Untitled (Autodesk Fusion 360 design; units mm, degrees)
Autodesk Fusion 360 part; units mm, degrees
sketch "Sketch1" plane through (0, 0, 0) normal (0, 1, 0) x (1, 0, 0)
  line L0 (38, 80) -> (-38, 80)
  line L1 (-38, 80) -> (-38, -80)
  line L2 (-38, -80) -> (38, -80)
  line L3 (38, -80) -> (38, 80)
  line L4 (38, 80) -> (-38, -80) construction
  line L5 (-38, 80) -> (38, -80) construction
  constraint perpendicular L0 L1
  constraint parallel L0 L2
  constraint parallel L1 L3
  constraint horizontal L0
  constraint coincident L4 origin
  constraint coincident L5 origin
extrude "Extrude1" add sketch "Sketch1" along normal blind 30
sketch "Sketch2" plane through (0, 0, 0) normal (0, -1, 0) x (1, 0, 0)
  line L0 (38, -80) -> (38, 80)
  line L1 (38, 80) -> (-38, 80)
  line L2 (-38, 80) -> (-38, -80)
  line L3 (-38, -80) -> (38, -80)
  line L4 (-8, 74) -> (8, 74)
  circle A0 centre (0, 0) radius 17.088
  dimension "d3" = 34.176
  constraint parallel L1 L4
  constraint coincident A0.centre origin
  measures "d3" diameter of A0
extrude "Extrude2" cut sketch "Sketch2" against normal up to surface (30 mm away) contours A0
